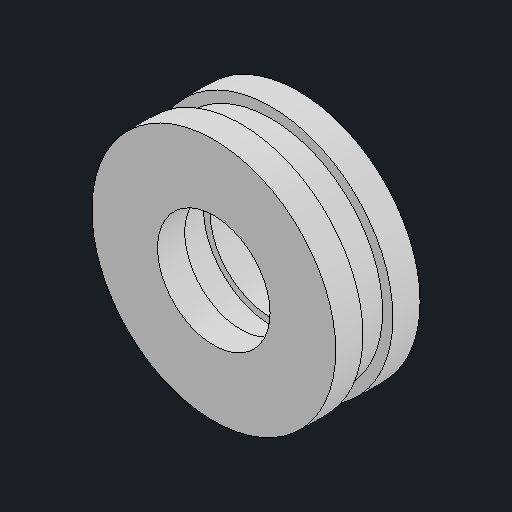
# Autodesk Inventor part: NTN-51101-thrust-envelope
Saved by Autodesk Inventor 2027.1 (Build 311270010, 270A)
## iProperties
Created: 2026-11-14
Part Number: NTN-51101-thrust-envelope
Material: Generic
Document SubType Name: Modeling
Designer: queezz
Density: 1 g/cm^3
Appearance: Default
Author: queezz
Autodesk Inventor part; units mm, degrees
ref_plane "Work Plane1" through (0, 0, 0) normal (0, 0, 1) x (1, 0, 0)
sketch "Housing washer layout" plane through (0, 0, 0) normal (0, 0, 1) x (1, 0, 0)
  circle A0 centre (0, 0) radius 6.5
  circle A1 centre (0, 0) radius 13
  constraints: 2 centre point
extrude "Housing washer" add sketch "Housing washer layout" along normal blind 2.9
ref_plane "Work Plane2" through (0, 0, 2.9) normal (0, 0, 1) x (1, 0, 0)
sketch "Cage envelope layout" plane through (0, 0, 2.9) normal (0, 0, 1) x (1, 0, 0)
  circle A0 centre (0, 0) radius 7.2
  circle A1 centre (0, 0) radius 11.9
  constraints: 2 centre point
extrude "Cage envelope" add sketch "Cage envelope layout" along normal blind 3.2 separate body
ref_plane "Work Plane3" through (0, 0, 6.1) normal (0, 0, 1) x (1, 0, 0)
sketch "Shaft washer layout" plane through (0, 0, 6.1) normal (0, 0, 1) x (1, 0, 0)
  circle A0 centre (0, 0) radius 6
  circle A1 centre (0, 0) radius 13
  constraints: 2 centre point
extrude "Shaft washer" add sketch "Shaft washer layout" along normal blind 2.9 separate body
body "Solid1"
body "Solid2"
body "Solid3"
